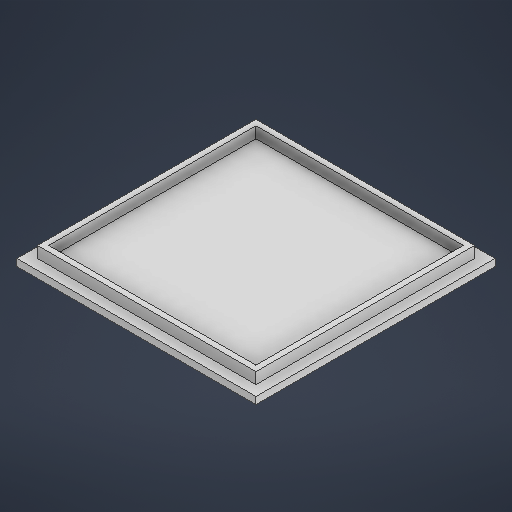
# Autodesk Inventor part: APRILTAGMOUNT
Saved by Autodesk Inventor 2026.2 (Build 302298000, 298)
## iProperties
Created: 2026-10-11
Part Number: APRILTAGMOUNT
Material: Generic
Document SubType Name: Modeling
Designer: Brian Wang
Density: 1 g/cm^3
Appearance: Default
Author: Brian Wang
Autodesk Inventor part; units mm, degrees
ref_plane "YZ Plane" through (0, 0, 0) normal (1, 0, 0) x (0, 1, 0)
ref_plane "XZ Plane" through (0, 0, 0) normal (0, 1, 0) x (-1, 0, 0)
ref_plane "XY Plane" through (0, 0, 0) normal (0, 0, 1) x (1, 0, 0)
sketch "Sketch1" plane through (0, 0, 0) normal (0, 1, 0) x (-1, 0, 0)
  line L0 (43.9802, 50.9172) -> (-41.0198, 50.9172)
  line L1 (-41.0198, 50.9172) -> (-41.0198, -34.0828)
  line L2 (-41.0198, -34.0828) -> (43.9802, -34.0828)
  line L3 (43.9802, -34.0828) -> (43.9802, 50.9172)
  point P0 (0, 0)
  dimension "d0" = 85
  dimension "d1" = 85
  constraints: 8 end point, 2 parallel, 1 horizontal, 1 perpendicular
  measures "d0" distance of L2.end L1.end
  measures "d1" distance of L1.end L0.end
extrude "Extrusion1" add sketch "Sketch1" along normal blind 2.5
sketch "Sketch2" plane through (0, 2.5, 0) normal (0, 1, 0) x (1, 0, 0)
  line L0 (-40.3302, -47.2672) -> (37.3698, -47.2672)
  line L1 (37.3698, -47.2672) -> (37.3698, 30.4328)
  line L2 (37.3698, 30.4328) -> (-40.3302, 30.4328)
  line L3 (-40.3302, 30.4328) -> (-40.3302, -47.2672)
  line L4 (-43.9802, 34.0828) -> (-43.9802, -50.9172) projected
  line L5 (41.0198, 34.0828) -> (-43.9802, 34.0828) projected
  line L6 (-38.3302, -45.2672) -> (35.3698, -45.2672)
  line L7 (35.3698, -45.2672) -> (35.3698, 28.4328)
  line L8 (35.3698, 28.4328) -> (-38.3302, 28.4328)
  line L9 (-38.3302, 28.4328) -> (-38.3302, -45.2672)
  point P0 (0, 0)
  dimension "d4" = 77.7
  dimension "d5" = 77.7
  dimension "d6" = 3.65
  dimension "d7" = 3.65
  dimension "d8" = 73.7
  dimension "d9" = 73.7
  dimension "d10" = 2
  dimension "d11" = 2
  constraints: 16 end point, 4 parallel, 2 horizontal, 2 perpendicular
  measures "d4" distance of L1.end L2.end
  measures "d5" distance of L0.end L1.end
  measures "d6" distance between parallel lines of L4 L3
  measures "d7" distance between parallel lines of L5 L2
  measures "d8" distance of L7.end L8.end
  measures "d9" distance of L8.end L6.start
  measures "d10" distance between parallel lines of L2 L8
  measures "d11" distance between parallel lines of L3 L9
extrude "Extrusion2" add sketch "Sketch2" along normal blind 4
body "Solid1"
